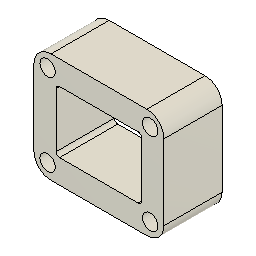
armacran v12 (Autodesk Fusion 360 archive; units mm, degrees)
design "espaciador_castor_wheel"
Autodesk Fusion 360 part; units mm, degrees
note: some values were not read from the file. Set by a fixed rule: which face or edge a step refers to.
sketch "Sketch1" plane through (0, 0, 0) normal (0, 0, 1) x (1, 0, 0)
  line L0 (19, -16) -> (-19, -16)
  line L1 (-19, -16) -> (-19, 16)
  line L2 (-19, 16) -> (19, 16)
  line L3 (19, 16) -> (19, -16)
  line L4 (19, -16) -> (-19, 16) construction
  line L5 (-19, -16) -> (19, 16) construction
  line L6 (15, -12) -> (-15, -12) construction
  line L7 (-15, -12) -> (-15, 12) construction
  line L8 (-15, 12) -> (15, 12) construction
  line L9 (15, 12) -> (15, -12) construction
  line L10 (15, -12) -> (-15, 12) construction
  line L11 (-15, -12) -> (15, 12) construction
  circle A0 centre (15, 12) radius 2.25
  line L12 (0, 0) -> (0, 16) construction
  line L13 (0, 0) -> (19, 0) construction
  circle A1 centre (-15, 12) radius 2.25
  circle A2 centre (-15, -12) radius 2.25
  circle A3 centre (15, -12) radius 2.25
  line L14 (12.5, -9) -> (-12.5, -9)
  line L15 (-12.5, -9) -> (-12.5, 9)
  line L16 (-12.5, 9) -> (12.5, 9)
  line L17 (12.5, 9) -> (12.5, -9)
  line L18 (12.5, -9) -> (-12.5, 9) construction
  line L19 (-12.5, -9) -> (12.5, 9) construction
  dimension "d1" = 38
  dimension "d2" = 32
  dimension "d3" = 24
  dimension "d4" = 30
  dimension "d5" = 4.5
  dimension "d6" = 18
  dimension "d7" = 25
  constraint horizontal L0
  constraint perpendicular L0 L1
  constraint parallel L0 L2
  constraint parallel L1 L3
  constraint coincident L4 L12.start
  constraint coincident L5 L12.start
  constraint coincident L12.start L13.start
  constraint horizontal L6
  constraint perpendicular L6 L7
  constraint parallel L6 L8
  constraint parallel L7 L9
  constraint coincident L10 L12.start
  constraint coincident L11 L12.start
  constraint coincident L8.end L9.start
  constraint midpoint L2 L12.end
  constraint midpoint L3 L13.end
  constraint symmetric A0 L12 A1
  constraint symmetric A0 L13 A3
  constraint symmetric L13 A1 A2
  constraint horizontal L14
  constraint perpendicular L14 L15
  constraint parallel L14 L16
  constraint parallel L15 L17
  constraint coincident L18 L12.start
  constraint coincident L19 L12.start
  measures "d1" distance of L1.end L2.end
  measures "d2" distance of L0.start L2.end
  measures "d3" distance of L6.start L8.end
  measures "d4" distance of L7.end L8.end
  measures "d5" diameter of A0
  measures "d6" distance of L14.start L16.end
  measures "d7" distance of L14.start L14.end
extrude "Extrude1" add sketch "Sketch1" along normal blind 17
fillet "Fillet1" radius 5 4 edges at (19, -16, 8.5) (-19, -16, 8.5) (19, 16, 8.5) (-19, 16, 8.5)
fillet "Fillet2" radius 1 4 edges at (-12.5, -9, 8.5) (-12.5, 9, 8.5) (12.5, 9, 8.5) (12.5, -9, 8.5)

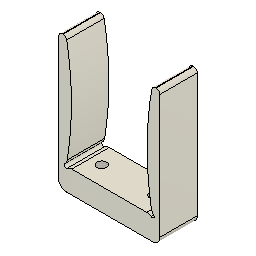
design "handler_lipo"
Autodesk Fusion 360 part; units mm, degrees
sketch "Sketch1" plane through (0, 0, 0) normal (0, 0, 1) x (1, 0, 0)
  line L0 (11.5, 15) -> (-11.5, 15)
  line L1 (-11.5, 15) -> (-11.5, -15)
  line L2 (-11.5, -15) -> (11.5, -15)
  line L3 (11.5, -15) -> (11.5, 15)
  line L4 (11.5, 15) -> (-11.5, -15) construction
  line L5 (-11.5, 15) -> (11.5, -15) construction
  line L6 (-14.5, 18) -> (-14.5, -18)
  line L7 (-14.5, -18) -> (14.5, -18)
  line L8 (14.5, -18) -> (14.5, 18)
  line L9 (14.5, 18) -> (-14.5, 18)
  circle A0 centre (-11.5, -15) radius 0.5
  circle A1 centre (11.5, -15) radius 0.5
  line L10 (11.5, 15) -> (14.5, 15)
  line L11 (0, 0) -> (0, 18) construction
  line L12 (-11.5, 15) -> (-14.5, 15)
  line L13 (-14.5, -5) -> (14.5, -5) construction
  arc A2 (-11.5, -15) -> (-11.5, 15) centre (-91.5, 0) ccw
  line L14 (7.5, 17.5) -> (-7.5, 17.5) construction
  line L15 (-7.5, 17.5) -> (-7.5, -17.5) construction
  line L16 (-7.5, -17.5) -> (7.5, -17.5) construction
  line L17 (7.5, -17.5) -> (7.5, 17.5) construction
  line L18 (7.5, 17.5) -> (-7.5, -17.5) construction
  line L19 (-7.5, 17.5) -> (7.5, -17.5) construction
  arc A3 (11.5, 15) -> (11.5, -15) centre (91.5, 0) ccw
  dimension "d1" = 23
  dimension "d2" = 30
  dimension "d3" = 3
  dimension "d4" = 1
  dimension "d5" = 15
  dimension "d20" = 5
  dimension "d21" = 80
  dimension "d22" = 15
  dimension "d23" = 35
  constraint horizontal L0
  constraint perpendicular L0 L1
  constraint parallel L0 L2
  constraint parallel L1 L3
  constraint coincident L4 L11.start
  constraint coincident L5 L11.start
  constraint coincident L11.start origin
  constraint coincident L1.end L2.start
  constraint coincident L2.end L3.start
  constraint equal A0 A1
  constraint coincident L3 L0.start
  constraint coincident L8 L10.end
  constraint perpendicular L3 L10
  constraint midpoint L9 L11.end
  constraint symmetric L0.start L11 L0.end
  constraint symmetric L10.end L11 L12.end
  constraint coincident L6 L13.start
  constraint coincident L8 L13.end
  constraint perpendicular L8 L13
  constraint horizontal L14
  constraint perpendicular L14 L15
  constraint parallel L14 L16
  constraint parallel L15 L17
  constraint coincident L18 L11.start
  constraint coincident L19 L11.start
  constraint symmetric L11 L0.end L0.start
  constraint symmetric L11 L1.end L2.end
  constraint symmetric L11 A2 A3
  measures "d1" distance of L1.end L2.end
  measures "d2" distance of L0.start L2.end
  measures "d4" diameter of A0
  measures "d5" distance of L11.start L10
  measures "d20" distance of L11.start L13
  measures "d21" distance of L1 A2.centre
  measures "d22" distance of L15.end L16.end
  measures "d23" distance of L14.end L15.end
extrude "Extrude1" add sketch "Sketch1" along normal mid plane 10 contours L1 L2 L3 L6 L7 L8 A0 A1 L10 L12 | L3 A1 A3 | L1 A0 A2 picked at (11.0906, 1.8973) picked at (-11.0906, 1.8973)
fillet "Fillet1" radius 2 2 edges at (-14.5, -18, 0) (14.5, -18, 0)
fillet "Fillet2" radius 2 4 edges at (11, -15, 0) (-11, -15, 0) (-11.4094, -14.5083, 0) (11.4094, -14.5083, 0)
sketch "Sketch2" plane through (0, -18, 0) normal (0, -1, 0) x (1, 0, 0)
  line L0 (12.5, -5) -> (12.5, 5)
  line L1 (12.5, 5) -> (-12.5, 5)
  line L2 (-12.5, 5) -> (-12.5, -5)
  line L3 (-12.5, -5) -> (12.5, -5)
  line L4 (7, 3) -> (-7, 3) construction
  line L5 (-7, 3) -> (-7, -3) construction
  line L6 (-7, -3) -> (7, -3) construction
  line L7 (7, -3) -> (7, 3) construction
  line L8 (7, 3) -> (-7, -3) construction
  line L9 (-7, 3) -> (7, -3) construction
  circle A0 centre (7, 3) radius 1.5 construction
  circle A1 centre (7, -3) radius 1.5 construction
  line L10 (0, 0) -> (0, 3) construction
  circle A2 centre (-7, 3) radius 1.5 construction
  circle A3 centre (-7, -3) radius 1.5 construction
  circle A4 centre (7, 0) radius 1.5
  circle A5 centre (-7, 0) radius 1.5
  dimension "d12" = 3
  dimension "d13" = 3
  dimension "d14" = 6
  dimension "d15" = 14
  dimension "d18" = 3
  dimension "d19" = 3
  constraint horizontal L4
  constraint perpendicular L4 L5
  constraint parallel L4 L6
  constraint parallel L5 L7
  constraint coincident L8 L10.start
  constraint coincident L9 L10.start
  constraint coincident L10.start origin
  constraint coincident L4.start L7.end
  constraint coincident L6.end L7.start
  constraint midpoint L4 L10.end
  constraint symmetric A0 L10 A2
  constraint symmetric A1 L10 A3
  constraint midpoint L7 A4.centre
  constraint midpoint L5 A5.centre
  measures "d12" diameter of A0
  measures "d13" diameter of A1
  measures "d14" distance of L4.start L6.end
  measures "d15" distance of L5.end L6.end
  measures "d18" diameter of A4
  measures "d19" diameter of A5
extrude "Extrude2" cut sketch "Sketch2" against normal blind 4 contours A4 | A5
move_face "OffsetFaces1" offset 1 1 faces at (-2.1507, -18, 3.7988)
move_face "OffsetFaces2" offset -1 2 faces at (14.5, 4.3333, 1.6667) (-14.5, -6.3333, 1.6667)
thread "Thread1" "ISO Metric profile 3.0 M3x0.5 6H" major diameter 3.086 minor diameter 2.529 pitch 0.5 angle 60 resizes the face on face at (-5.5075, -17.6667, -0.1494) on face at (8.4981, -17.6667, -0.0748)
fillet "Fillet3" radius 1 4 edges at (-11.5, 15, 0) (-13.5, 15, 0) (11.5, 15, 0) (13.5, 15, 0)
move_face "OffsetFaces3" offset 2 1 faces at (-2.1793, -19, 3.7257)

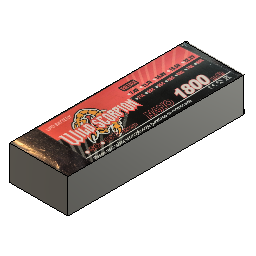
design "lipo_1800mah"
Autodesk Fusion 360 part; units mm, degrees
sketch "Sketch1" plane through (0, 0, 0) normal (0, 0, 1) x (1, 0, 0)
  line L0 (17.65, 10.35) -> (-17.65, 10.35)
  line L1 (-17.65, 10.35) -> (-17.65, -10.35)
  line L2 (-17.65, -10.35) -> (17.65, -10.35)
  line L3 (17.65, -10.35) -> (17.65, 10.35)
  line L4 (17.65, 10.35) -> (-17.65, -10.35) construction
  line L5 (-17.65, 10.35) -> (17.65, -10.35) construction
  dimension "d3" = 35.3
  dimension "d4" = 20.7
  constraint horizontal L0
  constraint perpendicular L0 L1
  constraint parallel L0 L2
  constraint parallel L1 L3
  constraint coincident L4 origin
  constraint coincident L5 origin
  measures "d3" distance of L1.end L2.end
  measures "d4" distance of L0.start L2.end
extrude "Extrude1" add sketch "Sketch1" along normal mid plane 108
fillet "Fillet1" radius 2 1 faces at (-5.8833, 3.45, -54)

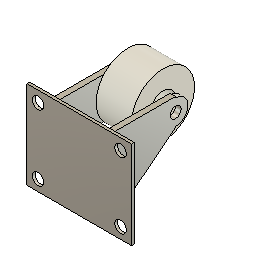
design "castor_wheel"
Autodesk Fusion 360 part; units mm, degrees
sketch "Sketch1" plane through (0, 0, 0) normal (0, 0, 1) x (1, 0, 0)
  line L0 (15, 12) -> (-15, 12) construction
  line L1 (-15, 12) -> (-15, -12) construction
  line L2 (-15, -12) -> (15, -12) construction
  line L3 (15, -12) -> (15, 12) construction
  line L4 (15, 12) -> (-15, -12) construction
  line L5 (-15, 12) -> (15, -12) construction
  circle A0 centre (15, 12) radius 2.1
  line L6 (0, 0) -> (0, 12) construction
  line L7 (0, 0) -> (15, 0) construction
  circle A1 centre (-15, 12) radius 2.1
  circle A2 centre (-15, -12) radius 2.1
  circle A3 centre (15, -12) radius 2.1
  line L8 (19, 16) -> (-19, 16)
  line L9 (-19, 16) -> (-19, -16)
  line L10 (-19, -16) -> (19, -16)
  line L11 (19, -16) -> (19, 16)
  line L12 (19, 16) -> (-19, -16) construction
  line L13 (-19, 16) -> (19, -16) construction
  dimension "d1" = 30
  dimension "d2" = 24
  dimension "d3" = 4.2
  dimension "d4" = 38
  dimension "d5" = 32
  constraint horizontal L0
  constraint perpendicular L0 L1
  constraint parallel L0 L2
  constraint parallel L1 L3
  constraint coincident L4 L6.start
  constraint coincident L5 L6.start
  constraint coincident L6.start L7.start
  constraint coincident L0.start L3.end
  constraint midpoint L0 L6.end
  constraint midpoint L3 L7.end
  constraint symmetric A0 L6 A1
  constraint symmetric A0 L7 A3
  constraint symmetric L7 A1 A2
  constraint horizontal L8
  constraint perpendicular L8 L9
  constraint parallel L8 L10
  constraint parallel L9 L11
  constraint coincident L12 L6.start
  constraint coincident L13 L6.start
  measures "d1" distance of L0.start L0.end
  measures "d2" distance of L0.start L2.end
  measures "d3" diameter of A0 A1
  measures "d4" distance of L8.start L8.end
  measures "d5" distance of L8.start L10.end
extrude "Extrude1" add sketch "Sketch1" along normal blind 1 makes body 1
sketch "Sketch2" plane through (0, 0, 0) normal (1, 0, 0) x (0, 0, -1)
  line L0 (0, 0) -> (23, 0) construction
  circle A0 centre (23, 0) radius 4.5 construction
  line L1 (0, 0) -> (23, 0) construction
  line L2 (23, 0) -> (23, 10) construction
  line L3 (23, 10) -> (0, 10) construction
  line L4 (0, 10) -> (0, 0) construction
  circle A1 centre (23, 10) radius 11.4
  circle A2 centre (23, 10) radius 4.5
  line L5 (0, 0) -> (23, 0)
  line L6 (23, 0) -> (23, 15)
  line L7 (23, 15) -> (0, 15)
  line L8 (0, 15) -> (0, 0)
  line L9 (0, 0) -> (7.5, 0)
  line L10 (7.5, 0) -> (7.5, 15)
  line L11 (7.5, 15) -> (0, 15)
  line L12 (0, 15) -> (0, 0)
  line L13 (0, 0) -> (23, 0)
  line L14 (23, 0) -> (23, -7)
  line L15 (23, -7) -> (0, -7)
  line L16 (0, -7) -> (0, 0)
  line L17 (7.5, -7) -> (23, 5.2)
  circle A3 centre (23, 10) radius 2
  dimension "d9" = 9
  dimension "d10" = 23
  dimension "d11" = 10
  dimension "d12" = 22.8
  dimension "d13" = 9
  dimension "d16" = 15
  dimension "d17" = 7.5
  dimension "d19" = 7
  dimension "d20" = 4.8
  dimension "d21" = 7.5
  dimension "d27" = 4
  constraint coincident L0.start L1.start
  constraint horizontal L0
  constraint coincident L0.end A0.centre
  constraint horizontal L1
  constraint vertical L2
  constraint horizontal L3
  constraint vertical L4
  constraint coincident L0.end L2
  constraint coincident L2.end L3.start
  constraint concentric A1 A2
  constraint horizontal L5
  constraint vertical L6
  constraint horizontal L7
  constraint vertical L8
  constraint horizontal L9
  constraint vertical L10
  constraint horizontal L11
  constraint vertical L12
  constraint coincident L7 L10.end
  constraint coincident L2.end L6
  constraint horizontal L13
  constraint vertical L14
  constraint horizontal L15
  constraint vertical L16
  constraint coincident L0.end L14
  constraint coincident L15 L17.start
  constraint coincident L2 L17.end
  constraint concentric A1 A3
  measures "d9" diameter of A0
  measures "d10" distance of L0.start L0.end
  measures "d11" distance of L0.end L2.end
  measures "d12" diameter of A1
  measures "d13" diameter of A2
  measures "d16" distance of L0.end L6.end
  measures "d17" distance of L0.start L10
  measures "d19" distance of L0.end L14.end
  measures "d20" distance of L2.end L17.end
  measures "d21" horizontal distance of L0.start L17.start
  measures "d27" diameter of A3
extrude "Extrude2" add sketch "Sketch2" along normal mid plane 12.9 separate body contours A1 A2 L6 L7 L14 | A1 A2 L6 L7 L17 | A1 L5 L13 L14 | A1 L5 L6 L13 L17 makes body 2
extrude "Extrude3" add sketch "Sketch2" along normal blind 2 from surface at 9 separate body contours A1 A2 L6 L7 L17 | A1 L5 L7 L10 L13 L17 | L5 L7 L8 L9 L10 L11 L12 L13 | L5 L9 L13 L15 L16 L17 | A2 L6 A3 | A2 L6 A3 makes body 3
mirror "Mirror1" about plane through (0, 0, 0) normal (1, 0, 0) of bodies 3 makes body 4
equation "d21 = d17"
